Autodesk Fusion 360 part; units mm, degrees
(part 2 of 28)
  line L578 (20.0688, 17.8511, -1.4859) -> (20.0988, 18.041, -1.4859)
  line L579 (20.0988, 18.041, -1.4859) -> (20.1582, 18.2238, -1.4859)
  line L580 (20.1582, 18.2238, -1.4859) -> (20.2455, 18.3951, -1.4859)
  line L581 (20.2455, 18.3951, -1.4859) -> (20.3585, 18.5506, -1.4859)
  line L582 (20.3585, 18.5506, -1.4859) -> (20.4944, 18.6865, -1.4859)
  line L583 (20.4944, 18.6865, -1.4859) -> (20.6499, 18.7995, -1.4859)
  line L584 (20.6499, 18.7995, -1.4859) -> (20.8212, 18.8868, -1.4859)
  line L585 (20.8212, 18.8868, -1.4859) -> (21.004, 18.9462, -1.4859)
  line L586 (21.004, 18.9462, -1.4859) -> (21.1939, 18.9762, -1.4859)
  line L587 (21.1939, 18.9762, -1.4859) -> (21.29, 18.98, -1.4859)
  line L588 (21.29, 18.98, -1.4859) -> (21.84, 18.98, -1.4859)
  line L589 (21.84, 18.98, -1.4859) -> (21.9361, 18.9762, -1.4859)
  line L590 (82.8961, 18.9762, -1.4859) -> (83.086, 18.9462, -1.4859)
  line L591 (83.086, 18.9462, -1.4859) -> (83.2688, 18.8868, -1.4859)
  line L592 (83.2688, 18.8868, -1.4859) -> (83.4401, 18.7995, -1.4859)
  line L593 (83.4401, 18.7995, -1.4859) -> (83.5956, 18.6865, -1.4859)
  line L594 (83.5956, 18.6865, -1.4859) -> (83.7315, 18.5506, -1.4859)
  line L595 (83.7315, 18.5506, -1.4859) -> (83.8445, 18.3951, -1.4859)
  line L596 (83.8445, 18.3951, -1.4859) -> (83.9318, 18.2238, -1.4859)
  line L597 (83.9318, 18.2238, -1.4859) -> (83.9912, 18.041, -1.4859)
  line L598 (83.9912, 18.041, -1.4859) -> (84.0212, 17.8511, -1.4859)
  line L599 (84.0212, 17.8511, -1.4859) -> (84.0212, 17.6589, -1.4859)
  line L600 (84.0212, 17.6589, -1.4859) -> (83.9912, 17.469, -1.4859)
  line L601 (83.9912, 17.469, -1.4859) -> (83.9318, 17.2862, -1.4859)
  line L602 (83.9318, 17.2862, -1.4859) -> (83.8445, 17.1149, -1.4859)
  line L603 (83.8445, 17.1149, -1.4859) -> (83.7315, 16.9594, -1.4859)
  line L604 (83.7315, 16.9594, -1.4859) -> (83.5956, 16.8235, -1.4859)
  line L605 (83.5956, 16.8235, -1.4859) -> (83.4401, 16.7105, -1.4859)
  line L606 (83.4401, 16.7105, -1.4859) -> (83.2688, 16.6232, -1.4859)
  line L607 (83.2688, 16.6232, -1.4859) -> (83.086, 16.5638, -1.4859)
  line L608 (83.086, 16.5638, -1.4859) -> (82.8961, 16.5338, -1.4859)
  line L609 (82.8961, 16.5338, -1.4859) -> (82.8, 16.53, -1.4859)
  line L610 (82.8, 16.53, -1.4859) -> (82.25, 16.53, -1.4859)
  line L611 (82.25, 16.53, -1.4859) -> (82.1539, 16.5338, -1.4859)
  line L612 (82.1539, 16.5338, -1.4859) -> (81.964, 16.5638, -1.4859)
  line L613 (81.964, 16.5638, -1.4859) -> (81.7812, 16.6232, -1.4859)
  line L614 (81.7812, 16.6232, -1.4859) -> (81.6099, 16.7105, -1.4859)
  line L615 (81.6099, 16.7105, -1.4859) -> (81.4544, 16.8235, -1.4859)
  line L616 (81.4544, 16.8235, -1.4859) -> (81.3185, 16.9594, -1.4859)
  line L617 (81.3185, 16.9594, -1.4859) -> (81.2055, 17.1149, -1.4859)
  line L618 (81.2055, 17.1149, -1.4859) -> (81.1182, 17.2862, -1.4859)
  line L619 (81.1182, 17.2862, -1.4859) -> (81.0588, 17.469, -1.4859)
  line L620 (81.0588, 17.469, -1.4859) -> (81.0288, 17.6589, -1.4859)
  line L621 (81.0288, 17.6589, -1.4859) -> (81.0288, 17.8511, -1.4859)
  line L622 (81.0288, 17.8511, -1.4859) -> (81.0588, 18.041, -1.4859)
  line L623 (81.0588, 18.041, -1.4859) -> (81.1182, 18.2238, -1.4859)
  line L624 (81.1182, 18.2238, -1.4859) -> (81.2055, 18.3951, -1.4859)
  line L625 (81.2055, 18.3951, -1.4859) -> (81.3185, 18.5506, -1.4859)
  line L626 (81.3185, 18.5506, -1.4859) -> (81.4544, 18.6865, -1.4859)
  line L627 (81.4544, 18.6865, -1.4859) -> (81.6099, 18.7995, -1.4859)
  line L628 (81.6099, 18.7995, -1.4859) -> (81.7812, 18.8868, -1.4859)
  line L629 (81.7812, 18.8868, -1.4859) -> (81.964, 18.9462, -1.4859)
  line L630 (81.964, 18.9462, -1.4859) -> (82.1539, 18.9762, -1.4859)
  line L631 (82.1539, 18.9762, -1.4859) -> (82.25, 18.98, -1.4859)
  line L632 (82.25, 18.98, -1.4859) -> (82.8, 18.98, -1.4859)
  line L633 (82.8, 18.98, -1.4859) -> (82.8961, 18.9762, -1.4859)
  line L634 (43.7633, 19.3436, -1.4859) -> (43.9556, 19.3053, -1.4859)
  line L635 (43.9556, 19.3053, -1.4859) -> (44.1367, 19.2303, -1.4859)
  line L636 (44.1367, 19.2303, -1.4859) -> (44.2997, 19.1214, -1.4859)
  line L637 (44.2997, 19.1214, -1.4859) -> (44.4383, 18.9828, -1.4859)
  line L638 (44.4383, 18.9828, -1.4859) -> (44.5472, 18.8198, -1.4859)
  line L639 (44.5472, 18.8198, -1.4859) -> (44.6222, 18.6387, -1.4859)
  line L640 (44.6222, 18.6387, -1.4859) -> (44.6605, 18.4464, -1.4859)
  line L641 (44.6605, 18.4464, -1.4859) -> (44.6605, 18.2504, -1.4859)
  line L642 (44.6605, 18.2504, -1.4859) -> (44.6222, 18.0581, -1.4859)
  line L643 (44.6222, 18.0581, -1.4859) -> (44.5472, 17.877, -1.4859)
  line L644 (44.5472, 17.877, -1.4859) -> (44.4383, 17.714, -1.4859)
  line L645 (44.4383, 17.714, -1.4859) -> (44.2997, 17.5754, -1.4859)
  line L646 (44.2997, 17.5754, -1.4859) -> (44.1367, 17.4665, -1.4859)
  line L647 (44.1367, 17.4665, -1.4859) -> (43.9556, 17.3915, -1.4859)
  line L648 (43.9556, 17.3915, -1.4859) -> (43.7633, 17.3532, -1.4859)
  line L649 (43.7633, 17.3532, -1.4859) -> (43.6653, 17.3484, -1.4859)
  line L650 (43.6653, 17.3484, -1.4859) -> (42.4653, 17.3484, -1.4859)
  line L651 (42.4653, 17.3484, -1.4859) -> (42.3673, 17.3532, -1.4859)
  line L652 (42.3673, 17.3532, -1.4859) -> (42.175, 17.3915, -1.4859)
  line L653 (42.175, 17.3915, -1.4859) -> (41.9939, 17.4665, -1.4859)
  line L654 (41.9939, 17.4665, -1.4859) -> (41.8309, 17.5754, -1.4859)
  line L655 (41.8309, 17.5754, -1.4859) -> (41.6923, 17.714, -1.4859)
  line L656 (41.6923, 17.714, -1.4859) -> (41.5834, 17.877, -1.4859)
  line L657 (41.5834, 17.877, -1.4859) -> (41.5083, 18.0581, -1.4859)
  line L658 (41.5083, 18.0581, -1.4859) -> (41.4701, 18.2504, -1.4859)
  line L659 (41.4701, 18.2504, -1.4859) -> (41.4701, 18.4464, -1.4859)
  line L660 (41.4701, 18.4464, -1.4859) -> (41.5083, 18.6387, -1.4859)
  line L661 (41.5083, 18.6387, -1.4859) -> (41.5834, 18.8198, -1.4859)
  line L662 (41.5834, 18.8198, -1.4859) -> (41.6923, 18.9828, -1.4859)
  line L663 (41.6923, 18.9828, -1.4859) -> (41.8309, 19.1214, -1.4859)
  line L664 (41.8309, 19.1214, -1.4859) -> (41.9939, 19.2303, -1.4859)
  line L665 (41.9939, 19.2303, -1.4859) -> (42.175, 19.3053, -1.4859)
  line L666 (42.175, 19.3053, -1.4859) -> (42.3673, 19.3436, -1.4859)
  line L667 (42.3673, 19.3436, -1.4859) -> (42.4653, 19.3484, -1.4859)
  line L668 (42.4653, 19.3484, -1.4859) -> (43.6653, 19.3484, -1.4859)
  line L669 (43.6653, 19.3484, -1.4859) -> (43.7633, 19.3436, -1.4859)
  line L670 (104.7233, 19.3436, -1.4859) -> (104.9156, 19.3053, -1.4859)
  line L671 (104.9156, 19.3053, -1.4859) -> (105.0967, 19.2303, -1.4859)
  line L672 (105.0967, 19.2303, -1.4859) -> (105.2597, 19.1214, -1.4859)
  line L673 (105.2597, 19.1214, -1.4859) -> (105.3983, 18.9828, -1.4859)
  line L674 (105.3983, 18.9828, -1.4859) -> (105.5072, 18.8198, -1.4859)
  line L675 (105.5072, 18.8198, -1.4859) -> (105.5822, 18.6387, -1.4859)
  line L676 (105.5822, 18.6387, -1.4859) -> (105.6205, 18.4464, -1.4859)
  line L677 (105.6205, 18.4464, -1.4859) -> (105.6205, 18.2504, -1.4859)
  line L678 (105.6205, 18.2504, -1.4859) -> (105.5822, 18.0581, -1.4859)
  line L679 (105.5822, 18.0581, -1.4859) -> (105.5072, 17.877, -1.4859)
  line L680 (105.5072, 17.877, -1.4859) -> (105.3983, 17.714, -1.4859)
  line L681 (105.3983, 17.714, -1.4859) -> (105.2597, 17.5754, -1.4859)
  line L682 (105.2597, 17.5754, -1.4859) -> (105.0967, 17.4665, -1.4859)
  line L683 (105.0967, 17.4665, -1.4859) -> (104.9156, 17.3915, -1.4859)
  line L684 (104.9156, 17.3915, -1.4859) -> (104.7233, 17.3532, -1.4859)
  line L685 (104.7233, 17.3532, -1.4859) -> (104.6253, 17.3484, -1.4859)
  line L686 (104.6253, 17.3484, -1.4859) -> (103.4253, 17.3484, -1.4859)
  line L687 (103.4253, 17.3484, -1.4859) -> (103.3273, 17.3532, -1.4859)
  line L688 (103.3273, 17.3532, -1.4859) -> (103.135, 17.3915, -1.4859)
  line L689 (103.135, 17.3915, -1.4859) -> (102.9539, 17.4665, -1.4859)
  line L690 (102.9539, 17.4665, -1.4859) -> (102.7909, 17.5754, -1.4859)
  line L691 (102.7909, 17.5754, -1.4859) -> (102.6523, 17.714, -1.4859)
  line L692 (102.6523, 17.714, -1.4859) -> (102.5434, 17.877, -1.4859)
  line L693 (102.5434, 17.877, -1.4859) -> (102.4683, 18.0581, -1.4859)
  line L694 (102.4683, 18.0581, -1.4859) -> (102.4301, 18.2504, -1.4859)
  line L695 (102.4301, 18.2504, -1.4859) -> (102.4301, 18.4464, -1.4859)
  line L696 (102.4301, 18.4464, -1.4859) -> (102.4683, 18.6387, -1.4859)
  line L697 (102.4683, 18.6387, -1.4859) -> (102.5434, 18.8198, -1.4859)
  line L698 (102.5434, 18.8198, -1.4859) -> (102.6523, 18.9828, -1.4859)
  line L699 (102.6523, 18.9828, -1.4859) -> (102.7909, 19.1214, -1.4859)
  line L700 (102.7909, 19.1214, -1.4859) -> (102.9539, 19.2303, -1.4859)
  line L701 (102.9539, 19.2303, -1.4859) -> (103.135, 19.3053, -1.4859)
  line L702 (103.135, 19.3053, -1.4859) -> (103.3273, 19.3436, -1.4859)
  line L703 (103.3273, 19.3436, -1.4859) -> (103.4253, 19.3484, -1.4859)
  line L704 (103.4253, 19.3484, -1.4859) -> (104.6253, 19.3484, -1.4859)
  line L705 (104.6253, 19.3484, -1.4859) -> (104.7233, 19.3436, -1.4859)
  line L706 (22.7914, 21.4641, -1.4859) -> (22.9046, 21.4087, -1.4859)
  line L707 (22.9046, 21.4087, -1.4859) -> (22.9937, 21.3196, -1.4859)
  line L708 (22.9937, 21.3196, -1.4859) -> (23.0491, 21.2064, -1.4859)
  line L709 (23.0491, 21.2064, -1.4859) -> (23.065, 21.0972, -1.4859)
  line L710 (23.065, 21.0972, -1.4859) -> (23.065, 19.4128, -1.4859)
  line L711 (23.065, 19.4128, -1.4859) -> (23.0491, 19.3036, -1.4859)
  line L712 (23.0491, 19.3036, -1.4859) -> (22.9937, 19.1904, -1.4859)
  line L713 (22.9937, 19.1904, -1.4859) -> (22.9046, 19.1013, -1.4859)
  line L714 (22.9046, 19.1013, -1.4859) -> (22.7914, 19.0459, -1.4859)
  line L715 (22.7914, 19.0459, -1.4859) -> (22.6822, 19.03, -1.4859)
  line L716 (22.6822, 19.03, -1.4859) -> (20.4478, 19.03, -1.4859)
  line L717 (20.4478, 19.03, -1.4859) -> (20.3386, 19.0459, -1.4859)
  line L718 (20.3386, 19.0459, -1.4859) -> (20.2254, 19.1013, -1.4859)
  line L719 (20.2254, 19.1013, -1.4859) -> (20.1363, 19.1904, -1.4859)
  line L720 (20.1363, 19.1904, -1.4859) -> (20.0809, 19.3036, -1.4859)
  line L721 (20.0809, 19.3036, -1.4859) -> (20.065, 19.4128, -1.4859)
  line L722 (20.065, 19.4128, -1.4859) -> (20.065, 21.0972, -1.4859)
  line L723 (20.065, 21.0972, -1.4859) -> (20.0809, 21.2064, -1.4859)
  line L724 (20.0809, 21.2064, -1.4859) -> (20.1363, 21.3196, -1.4859)
  line L725 (20.1363, 21.3196, -1.4859) -> (20.2254, 21.4087, -1.4859)
  line L726 (20.2254, 21.4087, -1.4859) -> (20.3386, 21.4641, -1.4859)
  line L727 (20.3386, 21.4641, -1.4859) -> (20.4478, 21.48, -1.4859)
  line L728 (20.4478, 21.48, -1.4859) -> (22.6822, 21.48, -1.4859)
  line L729 (22.6822, 21.48, -1.4859) -> (22.7914, 21.4641, -1.4859)
  line L730 (83.7514, 21.4641, -1.4859) -> (83.8646, 21.4087, -1.4859)
  line L731 (83.8646, 21.4087, -1.4859) -> (83.9537, 21.3196, -1.4859)
  line L732 (83.9537, 21.3196, -1.4859) -> (84.0091, 21.2064, -1.4859)
  line L733 (84.0091, 21.2064, -1.4859) -> (84.025, 21.0972, -1.4859)
  line L734 (84.025, 21.0972, -1.4859) -> (84.025, 19.4128, -1.4859)
  line L735 (84.025, 19.4128, -1.4859) -> (84.0091, 19.3036, -1.4859)
  line L736 (84.0091, 19.3036, -1.4859) -> (83.9537, 19.1904, -1.4859)
  line L737 (83.9537, 19.1904, -1.4859) -> (83.8646, 19.1013, -1.4859)
  line L738 (83.8646, 19.1013, -1.4859) -> (83.7514, 19.0459, -1.4859)
  line L739 (83.7514, 19.0459, -1.4859) -> (83.6422, 19.03, -1.4859)
  line L740 (83.6422, 19.03, -1.4859) -> (81.4078, 19.03, -1.4859)
  line L741 (81.4078, 19.03, -1.4859) -> (81.2986, 19.0459, -1.4859)
  line L742 (81.2986, 19.0459, -1.4859) -> (81.1854, 19.1013, -1.4859)
  line L743 (81.1854, 19.1013, -1.4859) -> (81.0963, 19.1904, -1.4859)
  line L744 (81.0963, 19.1904, -1.4859) -> (81.0409, 19.3036, -1.4859)
  line L745 (81.0409, 19.3036, -1.4859) -> (81.025, 19.4128, -1.4859)
  line L746 (81.025, 19.4128, -1.4859) -> (81.025, 21.0972, -1.4859)
  line L747 (81.025, 21.0972, -1.4859) -> (81.0409, 21.2064, -1.4859)
  line L748 (81.0409, 21.2064, -1.4859) -> (81.0963, 21.3196, -1.4859)
  line L749 (81.0963, 21.3196, -1.4859) -> (81.1854, 21.4087, -1.4859)
  line L750 (81.1854, 21.4087, -1.4859) -> (81.2986, 21.4641, -1.4859)
  line L751 (81.2986, 21.4641, -1.4859) -> (81.4078, 21.48, -1.4859)
  line L752 (81.4078, 21.48, -1.4859) -> (83.6422, 21.48, -1.4859)
  line L753 (83.6422, 21.48, -1.4859) -> (83.7514, 21.4641, -1.4859)
  line L754 (44.6653, 20.1184, -1.4859) -> (41.4653, 20.1184, -1.4859)
  line L755 (41.4653, 20.1184, -1.4859) -> (41.4653, 22.1184, -1.4859)
  line L756 (41.4653, 22.1184, -1.4859) -> (44.6653, 22.1184, -1.4859)
  line L757 (44.6653, 22.1184, -1.4859) -> (44.6653, 20.1184, -1.4859)
  line L758 (105.6253, 20.1184, -1.4859) -> (102.4253, 20.1184, -1.4859)
  line L759 (102.4253, 20.1184, -1.4859) -> (102.4253, 22.1184, -1.4859)
  line L760 (102.4253, 22.1184, -1.4859) -> (105.6253, 22.1184, -1.4859)
  line L761 (105.6253, 22.1184, -1.4859) -> (105.6253, 20.1184, -1.4859)
  line L762 (60.2983, 20.3076, -1.4859) -> (57.2983, 20.3076, -1.4859)
  line L763 (57.2983, 20.3076, -1.4859) -> (57.2983, 22.7576, -1.4859)
  line L764 (57.2983, 22.7576, -1.4859) -> (60.2983, 22.7576, -1.4859)
  line L765 (60.2983, 22.7576, -1.4859) -> (60.2983, 20.3076, -1.4859)
  line L766 (121.2583, 20.3076, -1.4859) -> (118.2583, 20.3076, -1.4859)
  line L767 (118.2583, 20.3076, -1.4859) -> (118.2583, 22.7576, -1.4859)
  line L768 (118.2583, 22.7576, -1.4859) -> (121.2583, 22.7576, -1.4859)
  line L769 (121.2583, 22.7576, -1.4859) -> (121.2583, 20.3076, -1.4859)
  line L770 (50.1088, 24.7613, -1.4859) -> (50.2954, 24.7007, -1.4859)
  line L771 (50.2954, 24.7007, -1.4859) -> (50.4702, 24.6116, -1.4859)
  line L772 (50.4702, 24.6116, -1.4859) -> (50.6288, 24.4963, -1.4859)
  line L773 (50.6288, 24.4963, -1.4859) -> (50.7675, 24.3576, -1.4859)
  line L774 (50.7675, 24.3576, -1.4859) -> (50.8828, 24.1989, -1.4859)
  line L775 (50.8828, 24.1989, -1.4859) -> (50.9719, 24.0242, -1.4859)
  line L776 (50.9719, 24.0242, -1.4859) -> (51.0325, 23.8376, -1.4859)
  line L777 (51.0325, 23.8376, -1.4859) -> (51.0632, 23.6439, -1.4859)
  line L778 (51.0632, 23.6439, -1.4859) -> (51.067, 23.5458, -1.4859)
  line L779 (51.067, 23.5458, -1.4859) -> (51.067, 23.0458, -1.4859)
  line L780 (51.067, 23.0458, -1.4859) -> (51.0632, 22.9477, -1.4859)
  line L781 (51.0632, 22.9477, -1.4859) -> (51.0325, 22.754, -1.4859)
  line L782 (51.0325, 22.754, -1.4859) -> (50.9719, 22.5675, -1.4859)
  line L783 (50.9719, 22.5675, -1.4859) -> (50.8828, 22.3927, -1.4859)
  line L784 (50.8828, 22.3927, -1.4859) -> (50.7675, 22.234, -1.4859)
  line L785 (50.7675, 22.234, -1.4859) -> (50.6288, 22.0953, -1.4859)
  line L786 (50.6288, 22.0953, -1.4859) -> (50.4702, 21.98, -1.4859)
  line L787 (50.4702, 21.98, -1.4859) -> (50.2954, 21.891, -1.4859)
  line L788 (50.2954, 21.891, -1.4859) -> (50.1088, 21.8304, -1.4859)
  line L789 (50.1088, 21.8304, -1.4859) -> (49.9151, 21.7997, -1.4859)
  line L790 (49.9151, 21.7997, -1.4859) -> (49.719, 21.7997, -1.4859)
  line L791 (49.719, 21.7997, -1.4859) -> (49.5252, 21.8304, -1.4859)
  line L792 (49.5252, 21.8304, -1.4859) -> (49.3387, 21.891, -1.4859)
  line L793 (49.3387, 21.891, -1.4859) -> (49.1639, 21.98, -1.4859)
  line L794 (49.1639, 21.98, -1.4859) -> (49.0052, 22.0953, -1.4859)
  line L795 (49.0052, 22.0953, -1.4859) -> (48.8665, 22.234, -1.4859)
  line L796 (48.8665, 22.234, -1.4859) -> (48.7512, 22.3927, -1.4859)
  line L797 (48.7512, 22.3927, -1.4859) -> (48.6622, 22.5675, -1.4859)
  line L798 (48.6622, 22.5675, -1.4859) -> (48.6016, 22.754, -1.4859)
  line L799 (48.6016, 22.754, -1.4859) -> (48.5709, 22.9477, -1.4859)
  line L800 (48.5709, 22.9477, -1.4859) -> (48.567, 23.0458, -1.4859)
  line L801 (48.567, 23.0458, -1.4859) -> (48.567, 23.5458, -1.4859)
  line L802 (48.567, 23.5458, -1.4859) -> (48.5709, 23.6439, -1.4859)
  line L803 (48.5709, 23.6439, -1.4859) -> (48.6016, 23.8376, -1.4859)
  line L804 (48.6016, 23.8376, -1.4859) -> (48.6622, 24.0242, -1.4859)
  line L805 (48.6622, 24.0242, -1.4859) -> (48.7512, 24.1989, -1.4859)
  line L806 (48.7512, 24.1989, -1.4859) -> (48.8665, 24.3576, -1.4859)
  line L807 (48.8665, 24.3576, -1.4859) -> (49.0052, 24.4963, -1.4859)
  line L808 (49.0052, 24.4963, -1.4859) -> (49.1639, 24.6116, -1.4859)
  line L809 (49.1639, 24.6116, -1.4859) -> (49.3387, 24.7007, -1.4859)
  line L810 (49.3387, 24.7007, -1.4859) -> (49.5252, 24.7613, -1.4859)
  line L811 (49.5252, 24.7613, -1.4859) -> (49.719, 24.792, -1.4859)
  line L812 (49.719, 24.792, -1.4859) -> (49.9151, 24.792, -1.4859)
  line L813 (49.9151, 24.792, -1.4859) -> (50.1088, 24.7613, -1.4859)
  line L814 (111.0688, 24.7613, -1.4859) -> (111.2554, 24.7007, -1.4859)
  line L815 (111.2554, 24.7007, -1.4859) -> (111.4302, 24.6116, -1.4859)
  line L816 (111.4302, 24.6116, -1.4859) -> (111.5888, 24.4963, -1.4859)
  line L817 (111.5888, 24.4963, -1.4859) -> (111.7275, 24.3576, -1.4859)
  line L818 (111.7275, 24.3576, -1.4859) -> (111.8428, 24.1989, -1.4859)
  line L819 (111.8428, 24.1989, -1.4859) -> (111.9319, 24.0242, -1.4859)
  line L820 (111.9319, 24.0242, -1.4859) -> (111.9925, 23.8376, -1.4859)
  line L821 (111.9925, 23.8376, -1.4859) -> (112.0232, 23.6439, -1.4859)
  line L822 (112.0232, 23.6439, -1.4859) -> (112.027, 23.5458, -1.4859)
  line L823 (112.027, 23.5458, -1.4859) -> (112.027, 23.0458, -1.4859)
  line L824 (112.027, 23.0458, -1.4859) -> (112.0232, 22.9477, -1.4859)
  line L825 (112.0232, 22.9477, -1.4859) -> (111.9925, 22.754, -1.4859)
  line L826 (111.9925, 22.754, -1.4859) -> (111.9319, 22.5675, -1.4859)
  line L827 (111.9319, 22.5675, -1.4859) -> (111.8428, 22.3927, -1.4859)
  line L828 (111.8428, 22.3927, -1.4859) -> (111.7275, 22.234, -1.4859)
  line L829 (111.7275, 22.234, -1.4859) -> (111.5888, 22.0953, -1.4859)
  line L830 (111.5888, 22.0953, -1.4859) -> (111.4302, 21.98, -1.4859)
  line L831 (111.4302, 21.98, -1.4859) -> (111.2554, 21.891, -1.4859)
  line L832 (111.2554, 21.891, -1.4859) -> (111.0688, 21.8304, -1.4859)
  line L833 (111.0688, 21.8304, -1.4859) -> (110.8751, 21.7997, -1.4859)
  line L834 (110.8751, 21.7997, -1.4859) -> (110.679, 21.7997, -1.4859)
  line L835 (110.679, 21.7997, -1.4859) -> (110.4852, 21.8304, -1.4859)
  line L836 (110.4852, 21.8304, -1.4859) -> (110.2987, 21.891, -1.4859)
  line L837 (110.2987, 21.891, -1.4859) -> (110.1239, 21.98, -1.4859)
  line L838 (110.1239, 21.98, -1.4859) -> (109.9652, 22.0953, -1.4859)
  line L839 (109.9652, 22.0953, -1.4859) -> (109.8265, 22.234, -1.4859)
  line L840 (109.8265, 22.234, -1.4859) -> (109.7112, 22.3927, -1.4859)
  line L841 (109.7112, 22.3927, -1.4859) -> (109.6222, 22.5675, -1.4859)
  line L842 (109.6222, 22.5675, -1.4859) -> (109.5616, 22.754, -1.4859)
  line L843 (109.5616, 22.754, -1.4859) -> (109.5309, 22.9477, -1.4859)
  line L844 (109.5309, 22.9477, -1.4859) -> (109.527, 23.0458, -1.4859)
  line L845 (109.527, 23.0458, -1.4859) -> (109.527, 23.5458, -1.4859)
  line L846 (109.527, 23.5458, -1.4859) -> (109.5309, 23.6439, -1.4859)
  line L847 (109.5309, 23.6439, -1.4859) -> (109.5616, 23.8376, -1.4859)
  line L848 (109.5616, 23.8376, -1.4859) -> (109.6222, 24.0242, -1.4859)
  line L849 (109.6222, 24.0242, -1.4859) -> (109.7112, 24.1989, -1.4859)
  line L850 (109.7112, 24.1989, -1.4859) -> (109.8265, 24.3576, -1.4859)
  line L851 (109.8265, 24.3576, -1.4859) -> (109.9652, 24.4963, -1.4859)
  line L852 (109.9652, 24.4963, -1.4859) -> (110.1239, 24.6116, -1.4859)
  line L853 (110.1239, 24.6116, -1.4859) -> (110.2987, 24.7007, -1.4859)
  line L854 (110.2987, 24.7007, -1.4859) -> (110.4852, 24.7613, -1.4859)
  line L855 (110.4852, 24.7613, -1.4859) -> (110.679, 24.792, -1.4859)
  line L856 (110.679, 24.792, -1.4859) -> (110.8751, 24.792, -1.4859)
  line L857 (110.8751, 24.792, -1.4859) -> (111.0688, 24.7613, -1.4859)
  line L858 (59.1694, 25.2939, -1.4859) -> (59.3593, 25.2638, -1.4859)
  line L859 (59.3593, 25.2638, -1.4859) -> (59.5421, 25.2044, -1.4859)
  line L860 (59.5421, 25.2044, -1.4859) -> (59.7134, 25.1171, -1.4859)
  line L861 (59.7134, 25.1171, -1.4859) -> (59.8689, 25.0041, -1.4859)
  line L862 (59.8689, 25.0041, -1.4859) -> (60.0048, 24.8682, -1.4859)
  line L863 (60.0048, 24.8682, -1.4859) -> (60.1178, 24.7127, -1.4859)
  line L864 (60.1178, 24.7127, -1.4859) -> (60.2051, 24.5414, -1.4859)
  line L865 (60.2051, 24.5414, -1.4859) -> (60.2645, 24.3586, -1.4859)
  line L866 (60.2645, 24.3586, -1.4859) -> (60.2945, 24.1687, -1.4859)
  line L867 (60.2945, 24.1687, -1.4859) -> (60.2945, 23.9765, -1.4859)
  line L868 (60.2945, 23.9765, -1.4859) -> (60.2645, 23.7867, -1.4859)
  line L869 (60.2645, 23.7867, -1.4859) -> (60.2051, 23.6038, -1.4859)
  line L870 (60.2051, 23.6038, -1.4859) -> (60.1178, 23.4326, -1.4859)
  line L871 (60.1178, 23.4326, -1.4859) -> (60.0048, 23.2771, -1.4859)
  line L872 (60.0048, 23.2771, -1.4859) -> (59.8689, 23.1411, -1.4859)
  line L873 (59.8689, 23.1411, -1.4859) -> (59.7134, 23.0281, -1.4859)
  line L874 (59.7134, 23.0281, -1.4859) -> (59.5421, 22.9409, -1.4859)
  line L875 (59.5421, 22.9409, -1.4859) -> (59.3593, 22.8815, -1.4859)
  line L876 (59.3593, 22.8815, -1.4859) -> (59.1694, 22.8514, -1.4859)
  line L877 (59.1694, 22.8514, -1.4859) -> (59.0733, 22.8476, -1.4859)
  line L878 (59.0733, 22.8476, -1.4859) -> (58.5233, 22.8476, -1.4859)
  line L879 (58.5233, 22.8476, -1.4859) -> (58.4272, 22.8514, -1.4859)
  line L880 (58.4272, 22.8514, -1.4859) -> (58.2373, 22.8815, -1.4859)
  line L881 (58.2373, 22.8815, -1.4859) -> (58.0545, 22.9409, -1.4859)
  line L882 (58.0545, 22.9409, -1.4859) -> (57.8833, 23.0281, -1.4859)
  line L883 (57.8833, 23.0281, -1.4859) -> (57.7277, 23.1411, -1.4859)
  line L884 (57.7277, 23.1411, -1.4859) -> (57.5918, 23.2771, -1.4859)
  line L885 (57.5918, 23.2771, -1.4859) -> (57.4788, 23.4326, -1.4859)
  line L886 (57.4788, 23.4326, -1.4859) -> (57.3916, 23.6038, -1.4859)
  line L887 (57.3916, 23.6038, -1.4859) -> (57.3322, 23.7867, -1.4859)
  line L888 (57.3322, 23.7867, -1.4859) -> (57.3021, 23.9765, -1.4859)
  line L889 (57.3021, 23.9765, -1.4859) -> (57.3021, 24.1687, -1.4859)
  line L890 (57.3021, 24.1687, -1.4859) -> (57.3322, 24.3586, -1.4859)
  line L891 (57.3322, 24.3586, -1.4859) -> (57.3916, 24.5414, -1.4859)
  line L892 (57.3916, 24.5414, -1.4859) -> (57.4788, 24.7127, -1.4859)
  line L893 (57.4788, 24.7127, -1.4859) -> (57.5918, 24.8682, -1.4859)
  line L894 (57.5918, 24.8682, -1.4859) -> (57.7277, 25.0041, -1.4859)
  line L895 (57.7277, 25.0041, -1.4859) -> (57.8833, 25.1171, -1.4859)
  line L896 (57.8833, 25.1171, -1.4859) -> (58.0545, 25.2044, -1.4859)
  line L897 (58.0545, 25.2044, -1.4859) -> (58.2373, 25.2638, -1.4859)
  line L898 (58.2373, 25.2638, -1.4859) -> (58.4272, 25.2939, -1.4859)
  line L899 (58.4272, 25.2939, -1.4859) -> (58.5233, 25.2976, -1.4859)
  line L900 (58.5233, 25.2976, -1.4859) -> (59.0733, 25.2976, -1.4859)
  line L901 (59.0733, 25.2976, -1.4859) -> (59.1694, 25.2939, -1.4859)
  line L902 (120.1294, 25.2939, -1.4859) -> (120.3193, 25.2638, -1.4859)
  line L903 (120.3193, 25.2638, -1.4859) -> (120.5021, 25.2044, -1.4859)
  line L904 (120.5021, 25.2044, -1.4859) -> (120.6734, 25.1171, -1.4859)
  line L905 (120.6734, 25.1171, -1.4859) -> (120.8289, 25.0041, -1.4859)
  line L906 (120.8289, 25.0041, -1.4859) -> (120.9648, 24.8682, -1.4859)
  line L907 (120.9648, 24.8682, -1.4859) -> (121.0778, 24.7127, -1.4859)
  line L908 (121.0778, 24.7127, -1.4859) -> (121.1651, 24.5414, -1.4859)
  line L909 (121.1651, 24.5414, -1.4859) -> (121.2245, 24.3586, -1.4859)
  line L910 (121.2245, 24.3586, -1.4859) -> (121.2545, 24.1687, -1.4859)
  line L911 (121.2545, 24.1687, -1.4859) -> (121.2545, 23.9765, -1.4859)
  line L912 (121.2545, 23.9765, -1.4859) -> (121.2245, 23.7867, -1.4859)
  line L913 (121.2245, 23.7867, -1.4859) -> (121.1651, 23.6038, -1.4859)
  line L914 (121.1651, 23.6038, -1.4859) -> (121.0778, 23.4326, -1.4859)
  line L915 (121.0778, 23.4326, -1.4859) -> (120.9648, 23.2771, -1.4859)
  line L916 (120.9648, 23.2771, -1.4859) -> (120.8289, 23.1411, -1.4859)
  line L917 (120.8289, 23.1411, -1.4859) -> (120.6734, 23.0281, -1.4859)
  line L918 (120.6734, 23.0281, -1.4859) -> (120.5021, 22.9409, -1.4859)
  line L919 (120.5021, 22.9409, -1.4859) -> (120.3193, 22.8815, -1.4859)
  line L920 (120.3193, 22.8815, -1.4859) -> (120.1294, 22.8514, -1.4859)
  line L921 (120.1294, 22.8514, -1.4859) -> (120.0333, 22.8476, -1.4859)
  line L922 (120.0333, 22.8476, -1.4859) -> (119.4833, 22.8476, -1.4859)
  line L923 (119.4833, 22.8476, -1.4859) -> (119.3872, 22.8514, -1.4859)
  line L924 (119.3872, 22.8514, -1.4859) -> (119.1973, 22.8815, -1.4859)
  line L925 (119.1973, 22.8815, -1.4859) -> (119.0145, 22.9409, -1.4859)
  line L926 (119.0145, 22.9409, -1.4859) -> (118.8433, 23.0281, -1.4859)
  line L927 (118.8433, 23.0281, -1.4859) -> (118.6877, 23.1411, -1.4859)
  line L928 (118.6877, 23.1411, -1.4859) -> (118.5518, 23.2771, -1.4859)
  line L929 (118.5518, 23.2771, -1.4859) -> (118.4388, 23.4326, -1.4859)
  line L930 (118.4388, 23.4326, -1.4859) -> (118.3516, 23.6038, -1.4859)
  line L931 (118.3516, 23.6038, -1.4859) -> (118.2922, 23.7867, -1.4859)
  line L932 (118.2922, 23.7867, -1.4859) -> (118.2621, 23.9765, -1.4859)
  line L933 (118.2621, 23.9765, -1.4859) -> (118.2621, 24.1687, -1.4859)
  line L934 (118.2621, 24.1687, -1.4859) -> (118.2922, 24.3586, -1.4859)
  line L935 (118.2922, 24.3586, -1.4859) -> (118.3516, 24.5414, -1.4859)
  line L936 (118.3516, 24.5414, -1.4859) -> (118.4388, 24.7127, -1.4859)
  line L937 (118.4388, 24.7127, -1.4859) -> (118.5518, 24.8682, -1.4859)
  line L938 (118.5518, 24.8682, -1.4859) -> (118.6877, 25.0041, -1.4859)
  line L939 (118.6877, 25.0041, -1.4859) -> (118.8433, 25.1171, -1.4859)
  line L940 (118.8433, 25.1171, -1.4859) -> (119.0145, 25.2044, -1.4859)
  line L941 (119.0145, 25.2044, -1.4859) -> (119.1973, 25.2638, -1.4859)
  line L942 (119.1973, 25.2638, -1.4859) -> (119.3872, 25.2939, -1.4859)
  line L943 (119.3872, 25.2939, -1.4859) -> (119.4833, 25.2976, -1.4859)
  line L944 (119.4833, 25.2976, -1.4859) -> (120.0333, 25.2976, -1.4859)
  line L945 (120.0333, 25.2976, -1.4859) -> (120.1294, 25.2939, -1.4859)
  line L946 (43.8215, 27.1487, -1.4859) -> (44.0138, 27.1104, -1.4859)
  line L947 (44.0138, 27.1104, -1.4859) -> (44.1949, 27.0354, -1.4859)
  line L948 (44.1949, 27.0354, -1.4859) -> (44.3579, 26.9265, -1.4859)
  line L949 (44.3579, 26.9265, -1.4859) -> (44.4965, 26.7879, -1.4859)
  line L950 (44.4965, 26.7879, -1.4859) -> (44.6054, 26.6249, -1.4859)
  line L951 (44.6054, 26.6249, -1.4859) -> (44.6804, 26.4438, -1.4859)
  line L952 (44.6804, 26.4438, -1.4859) -> (44.7187, 26.2515, -1.4859)
  line L953 (44.7187, 26.2515, -1.4859) -> (44.7187, 26.0555, -1.4859)
  line L954 (44.7187, 26.0555, -1.4859) -> (44.6804, 25.8632, -1.4859)
  line L955 (44.6804, 25.8632, -1.4859) -> (44.6054, 25.6821, -1.4859)
  line L956 (44.6054, 25.6821, -1.4859) -> (44.4965, 25.5191, -1.4859)
  line L957 (44.4965, 25.5191, -1.4859) -> (44.3579, 25.3805, -1.4859)
  line L958 (44.3579, 25.3805, -1.4859) -> (44.1949, 25.2716, -1.4859)
  line L959 (44.1949, 25.2716, -1.4859) -> (44.0138, 25.1965, -1.4859)
  line L960 (44.0138, 25.1965, -1.4859) -> (43.8215, 25.1583, -1.4859)
  line L961 (43.8215, 25.1583, -1.4859) -> (43.7235, 25.1535, -1.4859)
  line L962 (43.7235, 25.1535, -1.4859) -> (42.5235, 25.1535, -1.4859)
  line L963 (42.5235, 25.1535, -1.4859) -> (42.4255, 25.1583, -1.4859)
  line L964 (42.4255, 25.1583, -1.4859) -> (42.2332, 25.1965, -1.4859)
  line L965 (42.2332, 25.1965, -1.4859) -> (42.0521, 25.2716, -1.4859)
  line L966 (42.0521, 25.2716, -1.4859) -> (41.8891, 25.3805, -1.4859)
  line L967 (41.8891, 25.3805, -1.4859) -> (41.7505, 25.5191, -1.4859)
  line L968 (41.7505, 25.5191, -1.4859) -> (41.6416, 25.6821, -1.4859)
  line L969 (41.6416, 25.6821, -1.4859) -> (41.5665, 25.8632, -1.4859)
  line L970 (41.5665, 25.8632, -1.4859) -> (41.5283, 26.0555, -1.4859)
  line L971 (41.5283, 26.0555, -1.4859) -> (41.5283, 26.2515, -1.4859)
  line L972 (41.5283, 26.2515, -1.4859) -> (41.5665, 26.4438, -1.4859)
  line L973 (41.5665, 26.4438, -1.4859) -> (41.6416, 26.6249, -1.4859)
  line L974 (41.6416, 26.6249, -1.4859) -> (41.7505, 26.7879, -1.4859)
  line L975 (41.7505, 26.7879, -1.4859) -> (41.8891, 26.9265, -1.4859)
  line L976 (41.8891, 26.9265, -1.4859) -> (42.0521, 27.0354, -1.4859)
  line L977 (42.0521, 27.0354, -1.4859) -> (42.2332, 27.1104, -1.4859)
  line L978 (42.2332, 27.1104, -1.4859) -> (42.4255, 27.1487, -1.4859)
  line L979 (42.4255, 27.1487, -1.4859) -> (42.5235, 27.1535, -1.4859)
  line L980 (42.5235, 27.1535, -1.4859) -> (43.7235, 27.1535, -1.4859)
  line L981 (43.7235, 27.1535, -1.4859) -> (43.8215, 27.1487, -1.4859)
  line L982 (104.7815, 27.1487, -1.4859) -> (104.9738, 27.1104, -1.4859)
  line L983 (104.9738, 27.1104, -1.4859) -> (105.1549, 27.0354, -1.4859)
  line L984 (105.1549, 27.0354, -1.4859) -> (105.3179, 26.9265, -1.4859)
  line L985 (105.3179, 26.9265, -1.4859) -> (105.4565, 26.7879, -1.4859)
  line L986 (105.4565, 26.7879, -1.4859) -> (105.5654, 26.6249, -1.4859)
  line L987 (105.5654, 26.6249, -1.4859) -> (105.6404, 26.4438, -1.4859)
  line L988 (105.6404, 26.4438, -1.4859) -> (105.6787, 26.2515, -1.4859)
  line L989 (105.6787, 26.2515, -1.4859) -> (105.6787, 26.0555, -1.4859)
  line L990 (105.6787, 26.0555, -1.4859) -> (105.6404, 25.8632, -1.4859)
  line L991 (105.6404, 25.8632, -1.4859) -> (105.5654, 25.6821, -1.4859)
  line L992 (105.5654, 25.6821, -1.4859) -> (105.4565, 25.5191, -1.4859)
  line L993 (105.4565, 25.5191, -1.4859) -> (105.3179, 25.3805, -1.4859)
  line L994 (105.3179, 25.3805, -1.4859) -> (105.1549, 25.2716, -1.4859)
  line L995 (105.1549, 25.2716, -1.4859) -> (104.9738, 25.1965, -1.4859)
  line L996 (104.9738, 25.1965, -1.4859) -> (104.7815, 25.1583, -1.4859)
  line L997 (104.7815, 25.1583, -1.4859) -> (104.6835, 25.1535, -1.4859)
  line L998 (104.6835, 25.1535, -1.4859) -> (103.4835, 25.1535, -1.4859)
  line L999 (103.4835, 25.1535, -1.4859) -> (103.3855, 25.1583, -1.4859)
  line L1000 (103.3855, 25.1583, -1.4859) -> (103.1932, 25.1965, -1.4859)
  line L1001 (103.1932, 25.1965, -1.4859) -> (103.0121, 25.2716, -1.4859)
  line L1002 (103.0121, 25.2716, -1.4859) -> (102.8491, 25.3805, -1.4859)
  line L1003 (102.8491, 25.3805, -1.4859) -> (102.7105, 25.5191, -1.4859)
  line L1004 (102.7105, 25.5191, -1.4859) -> (102.6016, 25.6821, -1.4859)
  line L1005 (102.6016, 25.6821, -1.4859) -> (102.5265, 25.8632, -1.4859)
  line L1006 (102.5265, 25.8632, -1.4859) -> (102.4883, 26.0555, -1.4859)
  line L1007 (102.4883, 26.0555, -1.4859) -> (102.4883, 26.2515, -1.4859)
  line L1008 (102.4883, 26.2515, -1.4859) -> (102.5265, 26.4438, -1.4859)
  line L1009 (102.5265, 26.4438, -1.4859) -> (102.6016, 26.6249, -1.4859)
  line L1010 (102.6016, 26.6249, -1.4859) -> (102.7105, 26.7879, -1.4859)
  line L1011 (102.7105, 26.7879, -1.4859) -> (102.8491, 26.9265, -1.4859)
  line L1012 (102.8491, 26.9265, -1.4859) -> (103.0121, 27.0354, -1.4859)
  line L1013 (103.0121, 27.0354, -1.4859) -> (103.1932, 27.1104, -1.4859)
  line L1014 (103.1932, 27.1104, -1.4859) -> (103.3855, 27.1487, -1.4859)
  line L1015 (103.3855, 27.1487, -1.4859) -> (103.4835, 27.1535, -1.4859)
  line L1016 (103.4835, 27.1535, -1.4859) -> (104.6835, 27.1535, -1.4859)
  line L1017 (104.6835, 27.1535, -1.4859) -> (104.7815, 27.1487, -1.4859)
  line L1018 (32.6886, 30.3376, -1.4859) -> (32.8751, 30.277, -1.4859)
  line L1019 (32.8751, 30.277, -1.4859) -> (33.0499, 30.1879, -1.4859)
  line L1020 (33.0499, 30.1879, -1.4859) -> (33.2086, 30.0726, -1.4859)
  line L1021 (33.2086, 30.0726, -1.4859) -> (33.3473, 29.9339, -1.4859)
  line L1022 (33.3473, 29.9339, -1.4859) -> (33.4626, 29.7752, -1.4859)
  line L1023 (33.4626, 29.7752, -1.4859) -> (33.5516, 29.6005, -1.4859)
  line L1024 (33.5516, 29.6005, -1.4859) -> (33.5933, 29.4721, -1.4859)
  line L1025 (33.5933, 29.4721, -1.4859) -> (41.7199, 29.4721, -1.4859)
  line L1026 (41.7199, 29.4721, -1.4859) -> (41.7505, 29.5179, -1.4859)
  line L1027 (41.7505, 29.5179, -1.4859) -> (41.8891, 29.6565, -1.4859)
  line L1028 (41.8891, 29.6565, -1.4859) -> (42.0521, 29.7654, -1.4859)
  line L1029 (42.0521, 29.7654, -1.4859) -> (42.2332, 29.8404, -1.4859)
  line L1030 (42.2332, 29.8404, -1.4859) -> (42.4255, 29.8787, -1.4859)
  line L1031 (42.4255, 29.8787, -1.4859) -> (42.5235, 29.8835, -1.4859)
  line L1032 (42.5235, 29.8835, -1.4859) -> (43.7235, 29.8835, -1.4859)
  line L1033 (43.7235, 29.8835, -1.4859) -> (43.8215, 29.8787, -1.4859)
  line L1034 (43.8215, 29.8787, -1.4859) -> (44.0138, 29.8404, -1.4859)
  line L1035 (44.0138, 29.8404, -1.4859) -> (44.1949, 29.7654, -1.4859)
  line L1036 (44.1949, 29.7654, -1.4859) -> (44.3579, 29.6565, -1.4859)
  line L1037 (44.3579, 29.6565, -1.4859) -> (44.4965, 29.5179, -1.4859)
  line L1038 (44.4965, 29.5179, -1.4859) -> (44.6054, 29.3549, -1.4859)
  line L1039 (44.6054, 29.3549, -1.4859) -> (44.6804, 29.1738, -1.4859)
  line L1040 (44.6804, 29.1738, -1.4859) -> (44.7187, 28.9815, -1.4859)
  line L1041 (44.7187, 28.9815, -1.4859) -> (44.7187, 28.7855, -1.4859)
  line L1042 (44.7187, 28.7855, -1.4859) -> (44.6804, 28.5932, -1.4859)
  line L1043 (44.6804, 28.5932, -1.4859) -> (44.6054, 28.4121, -1.4859)
  line L1044 (44.6054, 28.4121, -1.4859) -> (44.4965, 28.2491, -1.4859)
  line L1045 (44.4965, 28.2491, -1.4859) -> (44.3579, 28.1105, -1.4859)
  line L1046 (44.3579, 28.1105, -1.4859) -> (44.1949, 28.0016, -1.4859)
  line L1047 (44.1949, 28.0016, -1.4859) -> (44.0138, 27.9265, -1.4859)
  line L1048 (44.0138, 27.9265, -1.4859) -> (43.8215, 27.8883, -1.4859)
  line L1049 (43.8215, 27.8883, -1.4859) -> (43.7235, 27.8835, -1.4859)
  line L1050 (43.7235, 27.8835, -1.4859) -> (42.5235, 27.8835, -1.4859)
  line L1051 (42.5235, 27.8835, -1.4859) -> (42.4255, 27.8883, -1.4859)
  line L1052 (42.4255, 27.8883, -1.4859) -> (42.2332, 27.9265, -1.4859)
  line L1053 (42.2332, 27.9265, -1.4859) -> (42.0521, 28.0016, -1.4859)
  line L1054 (42.0521, 28.0016, -1.4859) -> (41.8891, 28.1105, -1.4859)
  line L1055 (41.8891, 28.1105, -1.4859) -> (41.7505, 28.2491, -1.4859)
  line L1056 (41.7505, 28.2491, -1.4859) -> (41.7351, 28.2721, -1.4859)
  line L1057 (41.7351, 28.2721, -1.4859) -> (33.5933, 28.2721, -1.4859)
  line L1058 (33.5933, 28.2721, -1.4859) -> (33.5516, 28.1438, -1.4859)
  line L1059 (33.5516, 28.1438, -1.4859) -> (33.4626, 27.969, -1.4859)
  line L1060 (33.4626, 27.969, -1.4859) -> (33.3473, 27.8103, -1.4859)
  line L1061 (33.3473, 27.8103, -1.4859) -> (33.2086, 27.6716, -1.4859)
  line L1062 (33.2086, 27.6716, -1.4859) -> (33.0499, 27.5563, -1.4859)
  line L1063 (33.0499, 27.5563, -1.4859) -> (32.8751, 27.4673, -1.4859)
  line L1064 (32.8751, 27.4673, -1.4859) -> (32.6886, 27.4067, -1.4859)
  line L1065 (32.6886, 27.4067, -1.4859) -> (32.4948, 27.376, -1.4859)
  line L1066 (32.4948, 27.376, -1.4859) -> (32.2987, 27.376, -1.4859)
  line L1067 (32.2987, 27.376, -1.4859) -> (32.105, 27.4066, -1.4859)
  line L1068 (32.105, 27.4066, -1.4859) -> (31.9184, 27.4673, -1.4859)
  line L1069 (31.9184, 27.4673, -1.4859) -> (31.7436, 27.5563, -1.4859)
  line L1070 (31.7436, 27.5563, -1.4859) -> (31.585, 27.6716, -1.4859)
  line L1071 (31.585, 27.6716, -1.4859) -> (31.4463, 27.8103, -1.4859)
  line L1072 (31.4463, 27.8103, -1.4859) -> (31.331, 27.969, -1.4859)
  line L1073 (31.331, 27.969, -1.4859) -> (31.2419, 28.1438, -1.4859)
  line L1074 (31.2419, 28.1438, -1.4859) -> (31.1813, 28.3303, -1.4859)
  line L1075 (31.2063, 28.3553) -> (31.2063, 28.3553)
  line L1076 (31.1813, 28.3303, -1.4859) -> (23.318, 28.3303, -1.4859)
  line L1077 (23.318, 28.3303, -1.4859) -> (23.2976, 28.2903, -1.4859)
  line L1078 (23.2976, 28.2903, -1.4859) -> (23.1846, 28.1347, -1.4859)
  line L1079 (23.1846, 28.1347, -1.4859) -> (23.0487, 27.9988, -1.4859)
  line L1080 (23.0487, 27.9988, -1.4859) -> (22.8932, 27.8858, -1.4859)
  line L1081 (22.8932, 27.8858, -1.4859) -> (22.7219, 27.7986, -1.4859)
  line L1082 (22.7219, 27.7986, -1.4859) -> (22.5391, 27.7392, -1.4859)
  line L1083 (22.5391, 27.7392, -1.4859) -> (22.3492, 27.7091, -1.4859)
  line L1084 (22.3492, 27.7091, -1.4859) -> (22.2531, 27.7053, -1.4859)
  line L1085 (22.2531, 27.7053, -1.4859) -> (21.7031, 27.7053, -1.4859)
  line L1086 (21.7031, 27.7053, -1.4859) -> (21.607, 27.7091, -1.4859)
  line L1087 (21.607, 27.7091, -1.4859) -> (21.4171, 27.7392, -1.4859)
  line L1088 (21.4171, 27.7392, -1.4859) -> (21.2343, 27.7986, -1.4859)
  line L1089 (21.2343, 27.7986, -1.4859) -> (21.0631, 27.8858, -1.4859)
  line L1090 (21.0631, 27.8858, -1.4859) -> (20.9075, 27.9988, -1.4859)
  line L1091 (20.9075, 27.9988, -1.4859) -> (20.7716, 28.1347, -1.4859)
  line L1092 (20.7716, 28.1347, -1.4859) -> (20.6586, 28.2903, -1.4859)
  line L1093 (20.6586, 28.2903, -1.4859) -> (20.5714, 28.4615, -1.4859)
  line L1094 (20.5714, 28.4615, -1.4859) -> (20.512, 28.6443, -1.4859)
  line L1095 (20.512, 28.6443, -1.4859) -> (20.4819, 28.8342, -1.4859)
  line L1096 (20.4819, 28.8342, -1.4859) -> (20.4819, 29.0264, -1.4859)
  line L1097 (20.4819, 29.0264, -1.4859) -> (20.512, 29.2163, -1.4859)
  line L1098 (20.512, 29.2163, -1.4859) -> (20.5714, 29.3991, -1.4859)
  line L1099 (20.5714, 29.3991, -1.4859) -> (20.6586, 29.5704, -1.4859)
  line L1100 (20.6586, 29.5704, -1.4859) -> (20.7716, 29.7259, -1.4859)
  line L1101 (20.7716, 29.7259, -1.4859) -> (20.9075, 29.8618, -1.4859)
  line L1102 (20.9075, 29.8618, -1.4859) -> (21.0631, 29.9748, -1.4859)
  line L1103 (21.0631, 29.9748, -1.4859) -> (21.2343, 30.0621, -1.4859)
  line L1104 (21.2343, 30.0621, -1.4859) -> (21.4171, 30.1215, -1.4859)
  line L1105 (21.4171, 30.1215, -1.4859) -> (21.607, 30.1515, -1.4859)
  line L1106 (21.607, 30.1515, -1.4859) -> (21.7031, 30.1553, -1.4859)
  line L1107 (21.7031, 30.1553, -1.4859) -> (22.2531, 30.1553, -1.4859)
  line L1108 (22.2531, 30.1553, -1.4859) -> (22.3492, 30.1515, -1.4859)
  line L1109 (22.3492, 30.1515, -1.4859) -> (22.5391, 30.1215, -1.4859)
  line L1110 (22.5391, 30.1215, -1.4859) -> (22.7219, 30.0621, -1.4859)
  line L1111 (22.7219, 30.0621, -1.4859) -> (22.8932, 29.9748, -1.4859)
  line L1112 (22.8932, 29.9748, -1.4859) -> (23.0487, 29.8618, -1.4859)
  line L1113 (23.0487, 29.8618, -1.4859) -> (23.1846, 29.7259, -1.4859)
  line L1114 (23.1846, 29.7259, -1.4859) -> (23.2976, 29.5704, -1.4859)
  line L1115 (23.2976, 29.5704, -1.4859) -> (23.318, 29.5303, -1.4859)
  line L1116 (23.318, 29.5303, -1.4859) -> (31.2191, 29.5303, -1.4859)
  line L1117 (31.2191, 29.5303, -1.4859) -> (31.2419, 29.6005, -1.4859)
  line L1118 (31.2419, 29.6005, -1.4859) -> (31.331, 29.7752, -1.4859)
  line L1119 (31.331, 29.7752, -1.4859) -> (31.4463, 29.9339, -1.4859)
  line L1120 (31.4463, 29.9339, -1.4859) -> (31.585, 30.0726, -1.4859)
  line L1121 (31.585, 30.0726, -1.4859) -> (31.7436, 30.1879, -1.4859)
  line L1122 (31.7436, 30.1879, -1.4859) -> (31.9184, 30.277, -1.4859)
  line L1123 (31.9184, 30.277, -1.4859) -> (32.105, 30.3376, -1.4859)
  line L1124 (32.105, 30.3376, -1.4859) -> (32.2987, 30.3683, -1.4859)
  line L1125 (32.2987, 30.3683, -1.4859) -> (32.4948, 30.3683, -1.4859)
  line L1126 (32.4948, 30.3683, -1.4859) -> (32.6886, 30.3376, -1.4859)
  line L1127 (93.6486, 30.3376, -1.4859) -> (93.8351, 30.277, -1.4859)
  line L1128 (93.8351, 30.277, -1.4859) -> (94.0099, 30.1879, -1.4859)
  line L1129 (94.0099, 30.1879, -1.4859) -> (94.1686, 30.0726, -1.4859)
  line L1130 (94.1686, 30.0726, -1.4859) -> (94.3073, 29.9339, -1.4859)
  line L1131 (94.3073, 29.9339, -1.4859) -> (94.4226, 29.7752, -1.4859)
  line L1132 (94.4226, 29.7752, -1.4859) -> (94.5116, 29.6005, -1.4859)
  line L1133 (94.5116, 29.6005, -1.4859) -> (94.5533, 29.4721, -1.4859)
  line L1134 (94.5533, 29.4721, -1.4859) -> (102.6799, 29.4721, -1.4859)
  line L1135 (102.6799, 29.4721, -1.4859) -> (102.7105, 29.5179, -1.4859)
  line L1136 (102.7105, 29.5179, -1.4859) -> (102.8491, 29.6565, -1.4859)
  line L1137 (102.8491, 29.6565, -1.4859) -> (103.0121, 29.7654, -1.4859)
  line L1138 (103.0121, 29.7654, -1.4859) -> (103.1932, 29.8404, -1.4859)
  line L1139 (103.1932, 29.8404, -1.4859) -> (103.3855, 29.8787, -1.4859)
  line L1140 (103.3855, 29.8787, -1.4859) -> (103.4835, 29.8835, -1.4859)
  line L1141 (103.4835, 29.8835, -1.4859) -> (104.6835, 29.8835, -1.4859)
  line L1142 (104.6835, 29.8835, -1.4859) -> (104.7815, 29.8787, -1.4859)
  line L1143 (104.7815, 29.8787, -1.4859) -> (104.9738, 29.8404, -1.4859)
  line L1144 (104.9738, 29.8404, -1.4859) -> (105.1549, 29.7654, -1.4859)
  line L1145 (105.1549, 29.7654, -1.4859) -> (105.3179, 29.6565, -1.4859)
  line L1146 (105.3179, 29.6565, -1.4859) -> (105.4565, 29.5179, -1.4859)
  line L1147 (105.4565, 29.5179, -1.4859) -> (105.5654, 29.3549, -1.4859)
  line L1148 (105.5654, 29.3549, -1.4859) -> (105.6404, 29.1738, -1.4859)
  line L1149 (105.6404, 29.1738, -1.4859) -> (105.6787, 28.9815, -1.4859)
  line L1150 (105.6787, 28.9815, -1.4859) -> (105.6787, 28.7855, -1.4859)
  line L1151 (105.6787, 28.7855, -1.4859) -> (105.6404, 28.5932, -1.4859)
  line L1152 (105.6404, 28.5932, -1.4859) -> (105.5654, 28.4121, -1.4859)
  line L1153 (105.5654, 28.4121, -1.4859) -> (105.4565, 28.2491, -1.4859)
  line L1154 (105.4565, 28.2491, -1.4859) -> (105.3179, 28.1105, -1.4859)
  line L1155 (105.3179, 28.1105, -1.4859) -> (105.1549, 28.0016, -1.4859)
  line L1156 (105.1549, 28.0016, -1.4859) -> (104.9738, 27.9265, -1.4859)
  line L1157 (104.9738, 27.9265, -1.4859) -> (104.7815, 27.8883, -1.4859)
  line L1158 (104.7815, 27.8883, -1.4859) -> (104.6835, 27.8835, -1.4859)
  line L1159 (104.6835, 27.8835, -1.4859) -> (103.4835, 27.8835, -1.4859)
  line L1160 (103.4835, 27.8835, -1.4859) -> (103.3855, 27.8883, -1.4859)
  line L1161 (103.3855, 27.8883, -1.4859) -> (103.1932, 27.9265, -1.4859)
  line L1162 (103.1932, 27.9265, -1.4859) -> (103.0121, 28.0016, -1.4859)
  line L1163 (103.0121, 28.0016, -1.4859) -> (102.8491, 28.1105, -1.4859)
  line L1164 (102.8491, 28.1105, -1.4859) -> (102.7105, 28.2491, -1.4859)
  line L1165 (102.7105, 28.2491, -1.4859) -> (102.6951, 28.2721, -1.4859)
  line L1166 (102.6951, 28.2721, -1.4859) -> (94.5533, 28.2721, -1.4859)
  line L1167 (94.5533, 28.2721, -1.4859) -> (94.5116, 28.1438, -1.4859)
  line L1168 (94.5116, 28.1438, -1.4859) -> (94.4226, 27.969, -1.4859)
  line L1169 (94.4226, 27.969, -1.4859) -> (94.3073, 27.8103, -1.4859)
  line L1170 (94.3073, 27.8103, -1.4859) -> (94.1686, 27.6716, -1.4859)
  line L1171 (94.1686, 27.6716, -1.4859) -> (94.0099, 27.5563, -1.4859)
  line L1172 (94.0099, 27.5563, -1.4859) -> (93.8351, 27.4673, -1.4859)
  line L1173 (93.8351, 27.4673, -1.4859) -> (93.6486, 27.4067, -1.4859)
  line L1174 (93.6486, 27.4067, -1.4859) -> (93.4548, 27.376, -1.4859)
  line L1175 (93.4548, 27.376, -1.4859) -> (93.2587, 27.376, -1.4859)
  line L1176 (93.2587, 27.376, -1.4859) -> (93.065, 27.4066, -1.4859)
  line L1177 (93.065, 27.4066, -1.4859) -> (92.8784, 27.4673, -1.4859)
  line L1178 (92.8784, 27.4673, -1.4859) -> (92.7036, 27.5563, -1.4859)
  line L1179 (92.7036, 27.5563, -1.4859) -> (92.545, 27.6716, -1.4859)
  line L1180 (92.545, 27.6716, -1.4859) -> (92.4063, 27.8103, -1.4859)
  line L1181 (92.4063, 27.8103, -1.4859) -> (92.291, 27.969, -1.4859)
  line L1182 (92.291, 27.969, -1.4859) -> (92.2019, 28.1438, -1.4859)
  line L1183 (92.2019, 28.1438, -1.4859) -> (92.1413, 28.3303, -1.4859)
  line L1184 (92.1663, 28.3553) -> (92.1663, 28.3553)
  line L1185 (92.1413, 28.3303, -1.4859) -> (84.278, 28.3303, -1.4859)
  line L1186 (84.278, 28.3303, -1.4859) -> (84.2576, 28.2903, -1.4859)
  line L1187 (84.2576, 28.2903, -1.4859) -> (84.1446, 28.1347, -1.4859)
  line L1188 (84.1446, 28.1347, -1.4859) -> (84.0087, 27.9988, -1.4859)
  line L1189 (84.0087, 27.9988, -1.4859) -> (83.8532, 27.8858, -1.4859)
  line L1190 (83.8532, 27.8858, -1.4859) -> (83.6819, 27.7986, -1.4859)
  line L1191 (83.6819, 27.7986, -1.4859) -> (83.4991, 27.7392, -1.4859)
  line L1192 (83.4991, 27.7392, -1.4859) -> (83.3092, 27.7091, -1.4859)
  line L1193 (83.3092, 27.7091, -1.4859) -> (83.2131, 27.7053, -1.4859)
  line L1194 (83.2131, 27.7053, -1.4859) -> (82.6631, 27.7053, -1.4859)
  line L1195 (82.6631, 27.7053, -1.4859) -> (82.567, 27.7091, -1.4859)
  line L1196 (82.567, 27.7091, -1.4859) -> (82.3771, 27.7392, -1.4859)
  line L1197 (82.3771, 27.7392, -1.4859) -> (82.1943, 27.7986, -1.4859)
  line L1198 (82.1943, 27.7986, -1.4859) -> (82.0231, 27.8858, -1.4859)
  line L1199 (82.0231, 27.8858, -1.4859) -> (81.8675, 27.9988, -1.4859)
  line L1200 (81.8675, 27.9988, -1.4859) -> (81.7316, 28.1347, -1.4859)
  line L1201 (81.7316, 28.1347, -1.4859) -> (81.6186, 28.2903, -1.4859)
  line L1202 (81.6186, 28.2903, -1.4859) -> (81.5314, 28.4615, -1.4859)
  line L1203 (81.5314, 28.4615, -1.4859) -> (81.472, 28.6443, -1.4859)
  line L1204 (81.472, 28.6443, -1.4859) -> (81.4419, 28.8342, -1.4859)
  line L1205 (81.4419, 28.8342, -1.4859) -> (81.4419, 29.0264, -1.4859)
  line L1206 (81.4419, 29.0264, -1.4859) -> (81.472, 29.2163, -1.4859)
  line L1207 (81.472, 29.2163, -1.4859) -> (81.5314, 29.3991, -1.4859)
  line L1208 (81.5314, 29.3991, -1.4859) -> (81.6186, 29.5704, -1.4859)
  line L1209 (81.6186, 29.5704, -1.4859) -> (81.7316, 29.7259, -1.4859)
  line L1210 (81.7316, 29.7259, -1.4859) -> (81.8675, 29.8618, -1.4859)
  line L1211 (81.8675, 29.8618, -1.4859) -> (82.0231, 29.9748, -1.4859)
  line L1212 (82.0231, 29.9748, -1.4859) -> (82.1943, 30.0621, -1.4859)
  line L1213 (82.1943, 30.0621, -1.4859) -> (82.3771, 30.1215, -1.4859)
  line L1214 (82.3771, 30.1215, -1.4859) -> (82.567, 30.1515, -1.4859)
  line L1215 (82.567, 30.1515, -1.4859) -> (82.6631, 30.1553, -1.4859)
  line L1216 (82.6631, 30.1553, -1.4859) -> (83.2131, 30.1553, -1.4859)
  line L1217 (83.2131, 30.1553, -1.4859) -> (83.3092, 30.1515, -1.4859)
  line L1218 (83.3092, 30.1515, -1.4859) -> (83.4991, 30.1215, -1.4859)
  line L1219 (83.4991, 30.1215, -1.4859) -> (83.6819, 30.0621, -1.4859)
  line L1220 (83.6819, 30.0621, -1.4859) -> (83.8532, 29.9748, -1.4859)
  line L1221 (83.8532, 29.9748, -1.4859) -> (84.0087, 29.8618, -1.4859)
  line L1222 (84.0087, 29.8618, -1.4859) -> (84.1446, 29.7259, -1.4859)
  line L1223 (84.1446, 29.7259, -1.4859) -> (84.2576, 29.5704, -1.4859)
  line L1224 (84.2576, 29.5704, -1.4859) -> (84.278, 29.5303, -1.4859)
  line L1225 (84.278, 29.5303, -1.4859) -> (92.1791, 29.5303, -1.4859)
  line L1226 (92.1791, 29.5303, -1.4859) -> (92.2019, 29.6005, -1.4859)
  line L1227 (92.2019, 29.6005, -1.4859) -> (92.291, 29.7752, -1.4859)
  line L1228 (92.291, 29.7752, -1.4859) -> (92.4063, 29.9339, -1.4859)
  line L1229 (92.4063, 29.9339, -1.4859) -> (92.545, 30.0726, -1.4859)
  line L1230 (92.545, 30.0726, -1.4859) -> (92.7036, 30.1879, -1.4859)
  line L1231 (92.7036, 30.1879, -1.4859) -> (92.8784, 30.277, -1.4859)
  line L1232 (92.8784, 30.277, -1.4859) -> (93.065, 30.3376, -1.4859)
  line L1233 (93.065, 30.3376, -1.4859) -> (93.2587, 30.3683, -1.4859)
  line L1234 (93.2587, 30.3683, -1.4859) -> (93.4548, 30.3683, -1.4859)
  line L1235 (93.4548, 30.3683, -1.4859) -> (93.6486, 30.3376, -1.4859)
  line L1236 (50.1088, 32.3813, -1.4859) -> (50.2954, 32.3207, -1.4859)
  line L1237 (50.2954, 32.3207, -1.4859) -> (50.4702, 32.2316, -1.4859)
  line L1238 (50.4702, 32.2316, -1.4859) -> (50.6288, 32.1163, -1.4859)
  line L1239 (50.6288, 32.1163, -1.4859) -> (50.7675, 31.9776, -1.4859)
  line L1240 (50.7675, 31.9776, -1.4859) -> (50.8828, 31.8189, -1.4859)
  line L1241 (50.8828, 31.8189, -1.4859) -> (50.9719, 31.6442, -1.4859)
  line L1242 (50.9719, 31.6442, -1.4859) -> (51.0325, 31.4576, -1.4859)
  line L1243 (51.0325, 31.4576, -1.4859) -> (51.0632, 31.2639, -1.4859)
  line L1244 (51.0632, 31.2639, -1.4859) -> (51.067, 31.1658, -1.4859)
  line L1245 (51.067, 31.1658, -1.4859) -> (51.067, 30.6658, -1.4859)
  line L1246 (51.067, 30.6658, -1.4859) -> (51.0632, 30.5677, -1.4859)
  line L1247 (51.0632, 30.5677, -1.4859) -> (51.0325, 30.374, -1.4859)
  line L1248 (51.0325, 30.374, -1.4859) -> (50.9719, 30.1875, -1.4859)
  line L1249 (50.9719, 30.1875, -1.4859) -> (50.8828, 30.0127, -1.4859)
  line L1250 (50.8828, 30.0127, -1.4859) -> (50.7675, 29.854, -1.4859)
  line L1251 (50.7675, 29.854, -1.4859) -> (50.6288, 29.7153, -1.4859)
  line L1252 (50.6288, 29.7153, -1.4859) -> (50.4702, 29.6, -1.4859)
  line L1253 (50.4702, 29.6, -1.4859) -> (50.2954, 29.511, -1.4859)
  line L1254 (50.2954, 29.511, -1.4859) -> (50.1088, 29.4504, -1.4859)
  line L1255 (50.1088, 29.4504, -1.4859) -> (49.9151, 29.4197, -1.4859)
  line L1256 (49.9151, 29.4197, -1.4859) -> (49.719, 29.4197, -1.4859)
  line L1257 (49.719, 29.4197, -1.4859) -> (49.5252, 29.4504, -1.4859)
  line L1258 (49.5252, 29.4504, -1.4859) -> (49.3387, 29.511, -1.4859)
  line L1259 (49.3387, 29.511, -1.4859) -> (49.1639, 29.6, -1.4859)
  line L1260 (49.1639, 29.6, -1.4859) -> (49.0052, 29.7153, -1.4859)
  line L1261 (49.0052, 29.7153, -1.4859) -> (48.8665, 29.854, -1.4859)
  line L1262 (48.8665, 29.854, -1.4859) -> (48.7512, 30.0127, -1.4859)
  line L1263 (48.7512, 30.0127, -1.4859) -> (48.6622, 30.1875, -1.4859)
  line L1264 (48.6622, 30.1875, -1.4859) -> (48.6016, 30.374, -1.4859)
  line L1265 (48.6016, 30.374, -1.4859) -> (48.5709, 30.5677, -1.4859)
  line L1266 (48.5709, 30.5677, -1.4859) -> (48.567, 30.6658, -1.4859)
  line L1267 (48.567, 30.6658, -1.4859) -> (48.567, 31.1658, -1.4859)
  line L1268 (48.567, 31.1658, -1.4859) -> (48.5709, 31.2639, -1.4859)
  line L1269 (48.5709, 31.2639, -1.4859) -> (48.6016, 31.4576, -1.4859)
  line L1270 (48.6016, 31.4576, -1.4859) -> (48.6622, 31.6442, -1.4859)
  line L1271 (48.6622, 31.6442, -1.4859) -> (48.7512, 31.8189, -1.4859)
  line L1272 (48.7512, 31.8189, -1.4859) -> (48.8665, 31.9776, -1.4859)
  line L1273 (48.8665, 31.9776, -1.4859) -> (49.0052, 32.1163, -1.4859)
  line L1274 (49.0052, 32.1163, -1.4859) -> (49.1639, 32.2316, -1.4859)
  line L1275 (49.1639, 32.2316, -1.4859) -> (49.3387, 32.3207, -1.4859)